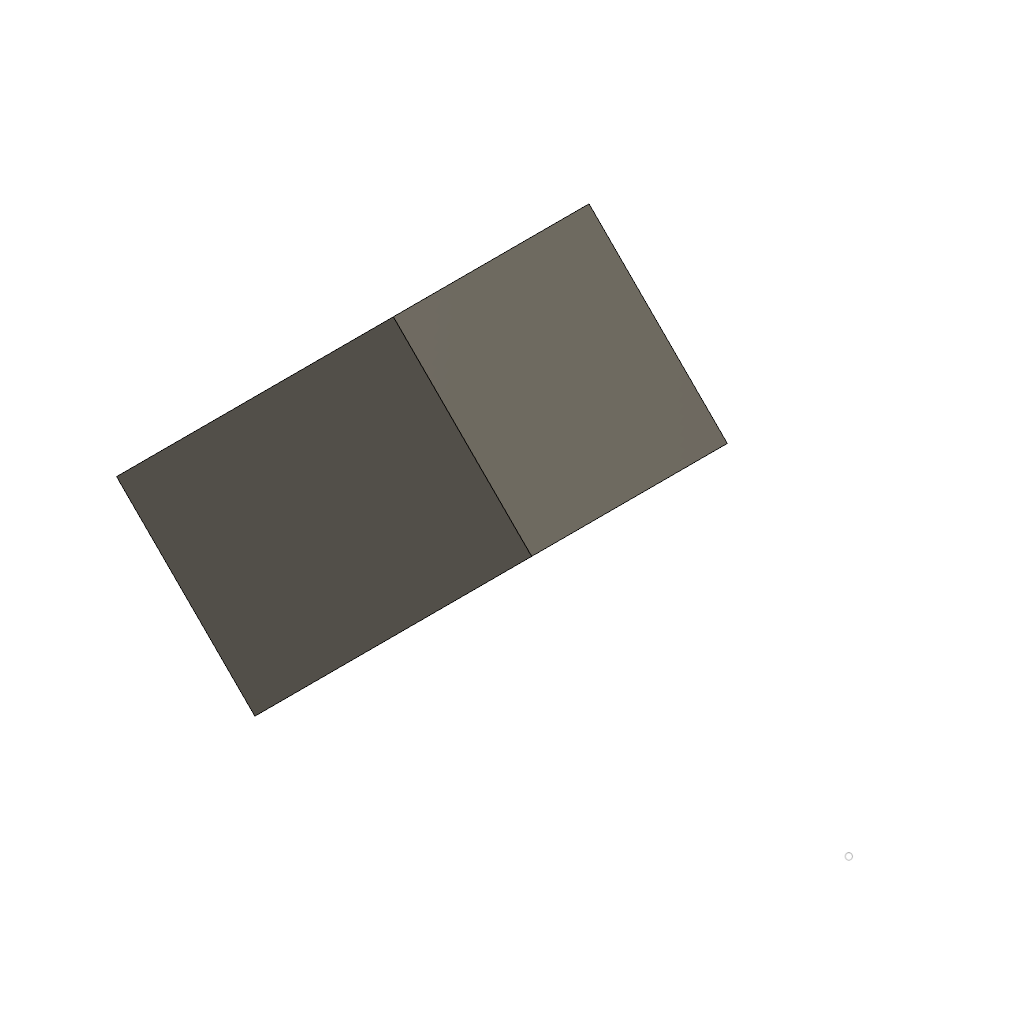
point_to_position_nested_design (Autodesk Fusion 360 design; units mm, degrees)
part number: 2026-10-20-21-37-54-355
part number: 2026-10-20-21-37-54-550
Autodesk Fusion 360 part; units mm, degrees
sketch "Sketch1" plane through (0, 0, 0) normal (0, 0, 1) x (1, 0, 0) in component "MovedComponent"
  line L0 (0, 0) -> (20, 0)
  line L1 (20, 0) -> (20, 10)
  line L2 (20, 10) -> (0, 10)
  line L3 (0, 10) -> (0, 0)
extrude "Extrude1" add sketch "Sketch1" along normal blind 10 in component "MovedComponent"
sketch "Sketch2" plane through (0, 0, 0) normal (0, 0, 1) x (1, 0, 0) in component "MovedComponent"
  point P0 (4, 8)
move_body "ProbeMove" bodies 1 to x (1, 0, 0) y (0, 1, 0) z (0, 0, 1) at (-13.8995, 23.1127, -3) in component "MovedComponent"
component "MovedComponent" placed x (0.707107, 0.707107, 0) y (-0.707107, 0.707107, 0) z (0, 0, 1) at (40, -20, 10)
named bodies: "MovedBody"
